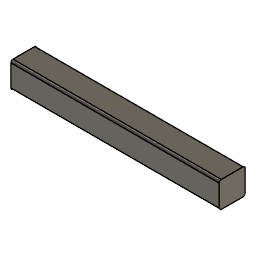
Front steering axle (Autodesk Fusion 360 design; units mm, degrees)
Autodesk Fusion 360 part; units mm, degrees
sketch "Sketch1" plane through (0, 0, 0) normal (1, 0, 0) x (0, 1, 0)
  line L0 (0, 3.175) -> (3.175, 3.175)
  line L1 (3.175, 3.175) -> (3.175, 0)
  line L2 (3.175, 0) -> (0, 0)
  line L3 (0, 0) -> (0, 3.175)
  dimension "d1" = 3.175
  dimension "d2" = 3.175
  constraint horizontal L0
  constraint vertical L1
  constraint horizontal L2
  constraint vertical L3
  constraint coincident L2.end L3.start
  measures "d1" distance of L0.end L1.end
  measures "d2" distance of L0.start L0.end
extrude "Extrude1" add sketch "Sketch1" along normal blind 25.4
fillet "Fillet1" radius 0.254 4 edges at (12.7, 0, 3.175) (12.7, 3.175, 3.175) (12.7, 0, 0) (12.7, 3.175, 0)
